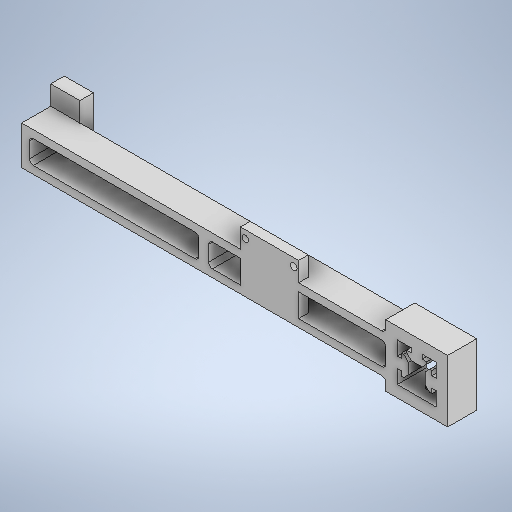
# Autodesk Inventor part: SUJETADOR_CAMARA_MODULO
Saved by Autodesk Inventor 2025.3 (Build 293356030, 356C)
## iProperties
Created: 2026-06-30
Part Number: SUJETADOR_CAMARA_MODULO
Material: Generic
Document SubType Name: Modeling
Designer: pablo
Density: 1 g/cm^3
Appearance: Default
Author: pablo
Autodesk Inventor part; units mm, degrees
ref_plane "YZ Plane" through (0, 0, 0) normal (1, 0, 0) x (0, 1, 0)
ref_plane "XZ Plane" through (0, 0, 0) normal (0, 1, 0) x (-1, 0, 0)
ref_plane "XY Plane" through (0, 0, 0) normal (0, 0, 1) x (1, 0, 0)
sketch "Sketch1" plane through (0, 0, 0) normal (0, 0, 1) x (1, 0, 0)
  line L0 (-2.8, -10) -> (-2.8, -7.8)
  line L1 (-2.8, -7.8) -> (-5.2, -7.8)
  line L2 (-5.2, -6.7) -> (-2.8, -4.3)
  line L3 (-7.8, -5.2) -> (-6.7, -5.2)
  line L4 (-6.7, -5.2) -> (-4.3, -2.8)
  line L5 (-2.8, -10) -> (-10, -10)
  line L6 (-7.8, -2.8) -> (-7.8, -5.2)
  line L7 (-7.8, -2.8) -> (-10, -2.8)
  line L8 (-10, -10) -> (-10, -2.8)
  line L9 (-5.2, -7.8) -> (-5.2, -6.7)
  line L10 (-4.3, -2.8) -> (-4.3, 0)
  line L11 (-4.3, 2.8) -> (-4.3, 0)
  line L12 (2.8, -10) -> (2.8, -7.8)
  line L13 (-10, -10) -> (10, -10)
  line L14 (2.8, -4.3) -> (0, -4.3)
  line L15 (5.2, -6.7) -> (2.8, -4.3)
  line L16 (6.7, -5.2) -> (4.3, -2.8)
  line L17 (2.8, -7.8) -> (5.2, -7.8)
  line L18 (2.8, -10) -> (10, -10)
  line L19 (5.2, -7.8) -> (5.2, -6.7)
  line L20 (-5.2, 6.7) -> (-2.8, 4.3)
  line L21 (-2.8, -4.3) -> (0, -4.3)
  line L22 (10, 10) -> (-10, 10)
  line L23 (2.8, 10) -> (10, 10)
  line L24 (-2.8, 7.8) -> (-5.2, 7.8)
  line L25 (-2.8, 10) -> (-2.8, 7.8)
  line L26 (2.8, 10) -> (2.8, 7.8)
  line L27 (2.8, 7.8) -> (5.2, 7.8)
  line L28 (-5.2, 7.8) -> (-5.2, 6.7)
  line L29 (5.2, 7.8) -> (5.2, 6.7)
  line L30 (-7.8, 5.2) -> (-6.7, 5.2)
  line L31 (-2.8, 4.3) -> (0, 4.3)
  line L32 (-6.7, 5.2) -> (-4.3, 2.8)
  line L33 (-7.8, 2.8) -> (-10, 2.8)
  line L34 (-7.8, 2.8) -> (-7.8, 5.2)
  line L35 (4.3, 2.8) -> (4.3, 0)
  line L36 (-10, 0) -> (10, 0) construction
  line L37 (10, -10) -> (10, 10)
  line L38 (-2.8, 10) -> (-10, 10)
  line L39 (0, -10) -> (0, 10) construction
  line L40 (-10, 10) -> (-10, 2.8)
  line L41 (7.8, 5.2) -> (6.7, 5.2)
  line L42 (2.8, 4.3) -> (0, 4.3)
  line L43 (5.2, 6.7) -> (2.8, 4.3)
  line L44 (7.8, 2.8) -> (10, 2.8)
  line L45 (6.7, 5.2) -> (4.3, 2.8)
  line L46 (7.8, 2.8) -> (7.8, 5.2)
  line L47 (10, 10) -> (10, 2.8)
  line L48 (7.8, -2.8) -> (10, -2.8)
  line L49 (7.8, -5.2) -> (6.7, -5.2)
  line L50 (7.8, -2.8) -> (7.8, -5.2)
  line L51 (10, 10) -> (10, -10) construction
  line L52 (10, -10) -> (10, -2.8)
  line L53 (4.3, -2.8) -> (4.3, 0)
  line L54 (-10, 10) -> (-10, -10)
  line L55 (16, 16) -> (-16, 16)
  line L56 (-16, 16) -> (-16, -16)
  line L57 (-16, -16) -> (16, -16)
  line L58 (16, -16) -> (16, 16)
  line L59 (16, 16) -> (-16, -16) construction
  line L60 (-16, 16) -> (16, -16) construction
  line L61 (-10, 10) -> (-16, 10)
  line L62 (-10, -10) -> (-16, -10)
  line L63 (-4.5, -16) -> (-12.5, -16)
  point P0 (0, 0)
  point P1 (0, 0)
  point P2 (0, 0)
  point P3 (-8.5, -16)
  point P4 (0, 0)
  point P5 (10, -2.8)
  dimension "d0" = 20
  dimension "d1" = 20
  dimension "d2" = 7.2
  dimension "d3" = 7.2
  dimension "d4" = 2.2
  dimension "d5" = 2.2
  dimension "d6" = 2.8
  dimension "d7" = 5.2
  dimension "d8" = 5.2
  dimension "d9" = 2.8
  dimension "d10" = 1.1
  dimension "d11" = 1.1
  dimension "d12" = 5.7
  dimension "d13" = 5.7
  dimension "d14" = 2.8
  dimension "d15" = 2.8
  dimension "d16" = 45
  dimension "d17" = 32
  dimension "d18" = 32
  constraints: 128 end point, 32 symmetric about line, 9 midpoint, 9 perpendicular, 7 point on line, 5 horizontal, 5 parallel, 2 coincident, 2 vertical, 1 horizontal alignment
  measures "d0" distance of L54.start L51.start
  measures "d1" distance of L51.start L13.end
  measures "d2" distance between parallel lines of L5 L7
  measures "d3" distance between parallel lines of L8 L0
  measures "d4" distance between parallel lines of L5 L1
  measures "d5" distance between parallel lines of L54 L6
  measures "d6" distance from line of L39.start L0
  measures "d7" distance from line of L39.start L9
  measures "d8" distance between parallel lines of L36 L3
  measures "d9" distance between parallel lines of L36 L7
  measures "d10" distance of L1.end L9.end
  measures "d11" distance of L6.end L4.start
  measures "d12" distance between parallel lines of L13 L21
  measures "d13" distance between parallel lines of L54 L10
  measures "d14" distance of L2.end L21.end
  measures "d15" distance of L10.start L10.end
  measures "d16" angle of L5 L2
  measures "d17" distance of L57.end L57.start
  measures "d18" distance between parallel lines of L55 L57
extrude "Extrusion1" add sketch "Sketch1" along normal blind 15 contours L13 L37 L22 L61 L56 L55 L58 L57 L62 L5 | L62 L56 L61 L40 L54 L8 | L54 L33 L34 L30 L32 L11 L10 L4 L3 L6 L7 | L48 L50 L49 L16 L53 L35 L45 L41 L46 L44 L37 | L22 L26 L27 L29 L43 L42 L31 L20 L28 L24 L25
sketch "Sketch2" plane through (-16, -16, 0) normal (0, -1, 0) x (1, 0, 0)
  line L0 (0, 0) -> (32, 0) projected
  line L1 (32, 0) -> (32, 15) projected
  line L2 (0, 15) -> (32, 15) projected
  line L3 (0, 0) -> (0, 15) projected
  point P0 (16, 0)
  point P1 (16, 7.5)
  point P2 (32, 7.5)
  point P3 (16, 0)
  constraints: 2 midpoint, 1 horizontal alignment, 1 vertical alignment
hole "Hole1" at (0, -16, 7.5) direction (0, 1, 0) diameter 4.2 depth 6
sketch "Sketch3" plane through (-16, -16, 0) normal (-1, 0, 0) x (0, 0, 1)
  line L0 (0, 32) -> (0, 0) projected
  line L1 (0, 0) -> (15, 0) projected
  line L2 (15, 32) -> (15, 0) projected
  line L3 (0, 32) -> (15, 32) projected
  line L4 (15, 26) -> (0, 26)
  line L5 (0, 26) -> (0, 22)
  line L6 (0, 22) -> (15, 22)
  line L7 (15, 22) -> (15, 26)
  line L8 (15, 10) -> (0, 10)
  line L9 (0, 10) -> (0, 6)
  line L10 (0, 6) -> (15, 6)
  line L11 (15, 6) -> (15, 10)
  line L12 (0, 32) -> (0, 0) projected
  point P0 (0, 16)
  point P1 (15, 8)
  point P2 (0, 16)
  point P3 (15, 24)
  point P4 (0, 16)
  dimension "d31" = 4
  dimension "d32" = 8
  dimension "d33" = 8
  dimension "d34" = 4
  constraints: 16 end point, 4 parallel, 4 point on line, 3 midpoint, 2 horizontal, 2 perpendicular, 2 other
  measures "d31" distance between parallel lines of L10 L8
  measures "d32" vertical distance of point (15, 8) point (0, 16)
  measures "d33" vertical distance of point (15, 24) point (0, 16)
  measures "d34" distance between parallel lines of L4 L6
extrude "Extrusion2" add sketch "Sketch3" along normal blind 188 contours L4 L2 L6 L0 | L8 L2 L10 L0
sketch "Sketch4" plane through (-16, 6, 0) normal (0, -1, 0) x (1, 0, 0)
  line L0 (0, 15) -> (0, 0) projected
  line L1 (0, 15) -> (-188, 15) projected
  line L2 (-188, 0) -> (-188, 15) projected
  line L3 (0, 0) -> (-188, 0) projected
  line L4 (0, 0) -> (-188, 0) projected
  line L5 (0, 15) -> (-188, 15) projected
  line L6 (-91.5, 0) -> (-96.5, 0)
  line L7 (-96.5, 0) -> (-96.5, 15)
  line L8 (-96.5, 15) -> (-91.5, 15)
  line L9 (-91.5, 15) -> (-91.5, 0)
  point P0 (16, 0)
  point P1 (-94, 15)
  point P2 (-94, 15)
  point P3 (-91.5, 0)
  point P4 (-96.5, 0)
  dimension "d37" = 5
  constraints: 8 end point, 2 midpoint, 2 parallel, 2 point on line, 1 coincident, 1 horizontal, 1 perpendicular
  measures "d37" distance between parallel lines of L7 L9
extrude "Extrusion3" add sketch "Sketch4" along normal up to surface (12 mm away) contours L9 L3 L7 L1
sketch "Sketch9" plane through (0, 0, 15) normal (0, 0, 1) x (1, 0, 0)
  line L0 (-112.5, 6) -> (-204, 6) projected
  line L1 (-112.5, 6) -> (-112.5, -6) projected
  line L2 (-112.5, -6) -> (-204, -6) projected
  line L3 (-16, 6) -> (-107.5, 6) projected
  line L4 (-16, 6) -> (-16, -6) projected
  line L5 (-16, -6) -> (-107.5, -6) projected
  line L6 (-107.5, 6) -> (-107.5, -6) projected
  line L7 (-16, -10) -> (-204, -10) projected
  line L8 (-16, -10) -> (-16, -16) projected
  line L9 (-16, -16) -> (16, -16) projected
  line L10 (16, -16) -> (16, 16) projected
  line L11 (16, 16) -> (-16, 16) projected
  line L12 (-16, 16) -> (-16, 10) projected
  line L13 (-16, 10) -> (-204, 10) projected
  line L14 (-10, -10) -> (-10, -2.8) projected
  line L15 (-10, -2.8) -> (-7.8, -2.8) projected
  line L16 (-7.8, -2.8) -> (-7.8, -5.2) projected
  line L17 (-7.8, -5.2) -> (-6.7, -5.2) projected
  line L18 (-6.7, -5.2) -> (-4.3, -2.8) projected
  line L19 (-4.3, -2.8) -> (-4.3, 2.8) projected
  line L20 (-4.3, 2.8) -> (-6.7, 5.2) projected
  line L21 (-6.7, 5.2) -> (-7.8, 5.2) projected
  line L22 (-7.8, 5.2) -> (-7.8, 2.8) projected
  line L23 (-7.8, 2.8) -> (-10, 2.8) projected
  line L24 (-10, 2.8) -> (-10, 10) projected
  line L25 (-10, 10) -> (-2.8, 10) projected
  line L26 (-2.8, 10) -> (-2.8, 7.8) projected
  line L27 (-2.8, 7.8) -> (-5.2, 7.8) projected
  line L28 (-5.2, 7.8) -> (-5.2, 6.7) projected
  line L29 (-5.2, 6.7) -> (-2.8, 4.3) projected
  line L30 (-2.8, 4.3) -> (2.8, 4.3) projected
  line L31 (2.8, 4.3) -> (5.2, 6.7) projected
  line L32 (5.2, 6.7) -> (5.2, 7.8) projected
  line L33 (5.2, 7.8) -> (2.8, 7.8) projected
  line L34 (2.8, 7.8) -> (2.8, 10) projected
  line L35 (2.8, 10) -> (10, 10) projected
  line L36 (10, 10) -> (10, 2.8) projected
  line L37 (10, 2.8) -> (7.8, 2.8) projected
  line L38 (7.8, 2.8) -> (7.8, 5.2) projected
  line L39 (7.8, 5.2) -> (6.7, 5.2) projected
  line L40 (6.7, 5.2) -> (4.3, 2.8) projected
  line L41 (4.3, 2.8) -> (4.3, -2.8) projected
  line L42 (4.3, -2.8) -> (6.7, -5.2) projected
  line L43 (6.7, -5.2) -> (7.8, -5.2) projected
  line L44 (7.8, -5.2) -> (7.8, -2.8) projected
  line L45 (7.8, -2.8) -> (10, -2.8) projected
  line L46 (10, -2.8) -> (10, -10) projected
  line L47 (10, -10) -> (-10, -10) projected
  line L48 (-61, 20) -> (-91, 20)
  line L49 (-91, 20) -> (-91, -10)
  line L50 (-91, -10) -> (-61, -10)
  line L51 (-61, -10) -> (-61, 20)
  line L52 (-16, -10) -> (-204, -10) projected
  line L53 (-204, -10) -> (-204, -6) projected
  line L54 (-204, 6) -> (-204, 10) projected
  point P0 (0, 0)
  point P1 (-16, 0)
  point P2 (-76, -10)
  dimension "d58" = 30
  dimension "d59" = 30
  dimension "d60" = 45
  constraints: 8 end point, 2 midpoint, 2 parallel, 1 horizontal, 1 perpendicular, 1 point on line
  measures "d58" distance of L49.end L50.end
  measures "d59" distance of L50.end L48.start
  measures "d60" distance between parallel lines of L8 L51
extrude "Extrusion7" add sketch "Sketch9" against normal blind 5 contours L49 L48 L51 L13 | L13 L51 L3 L49 | L3 L51 L5 L49 | L49 L5 L51 L7
sketch "Sketch10" plane through (0, 0, 15) normal (0, 0, 1) x (1, 0, 0)
  line L0 (-16, 6) -> (-61, 6) projected
  line L1 (-16, 6) -> (-16, -6) projected
  line L2 (-16, -6) -> (-61, -6) projected
  line L3 (-61, -6) -> (-61, 6) projected
  line L4 (-91, 6) -> (-91, -6) projected
  line L5 (-91, -6) -> (-107.5, -6) projected
  line L6 (-107.5, 6) -> (-107.5, -6) projected
  line L7 (-91, 6) -> (-107.5, 6) projected
  line L8 (-112.5, 6) -> (-204, 6) projected
  line L9 (-112.5, 6) -> (-112.5, -6) projected
  line L10 (-112.5, -6) -> (-204, -6) projected
  line L11 (-91, 10) -> (-204, 10) projected
  line L12 (-16, -10) -> (-204, -10) projected
  line L13 (-16, -10) -> (-16, -16) projected
  line L14 (-16, -16) -> (16, -16) projected
  line L15 (16, -16) -> (16, 16) projected
  line L16 (16, 16) -> (-16, 16) projected
  line L17 (-16, 16) -> (-16, 10) projected
  line L18 (-16, 10) -> (-61, 10) projected
  line L19 (-61, 10) -> (-61, 20) projected
  line L20 (-61, 20) -> (-91, 20) projected
  line L21 (-91, 20) -> (-91, 10) projected
  line L22 (-10, -10) -> (-10, -2.8) projected
  line L23 (-10, -2.8) -> (-7.8, -2.8) projected
  line L24 (-7.8, -2.8) -> (-7.8, -5.2) projected
  line L25 (-7.8, -5.2) -> (-6.7, -5.2) projected
  line L26 (-6.7, -5.2) -> (-4.3, -2.8) projected
  line L27 (-4.3, -2.8) -> (-4.3, 2.8) projected
  line L28 (-4.3, 2.8) -> (-6.7, 5.2) projected
  line L29 (-6.7, 5.2) -> (-7.8, 5.2) projected
  line L30 (-7.8, 5.2) -> (-7.8, 2.8) projected
  line L31 (-7.8, 2.8) -> (-10, 2.8) projected
  line L32 (-10, 2.8) -> (-10, 10) projected
  line L33 (-10, 10) -> (-2.8, 10) projected
  line L34 (-2.8, 10) -> (-2.8, 7.8) projected
  line L35 (-2.8, 7.8) -> (-5.2, 7.8) projected
  line L36 (-5.2, 7.8) -> (-5.2, 6.7) projected
  line L37 (-5.2, 6.7) -> (-2.8, 4.3) projected
  line L38 (-2.8, 4.3) -> (2.8, 4.3) projected
  line L39 (2.8, 4.3) -> (5.2, 6.7) projected
  line L40 (5.2, 6.7) -> (5.2, 7.8) projected
  line L41 (5.2, 7.8) -> (2.8, 7.8) projected
  line L42 (2.8, 7.8) -> (2.8, 10) projected
  line L43 (2.8, 10) -> (10, 10) projected
  line L44 (10, 10) -> (10, 2.8) projected
  line L45 (10, 2.8) -> (7.8, 2.8) projected
  line L46 (7.8, 2.8) -> (7.8, 5.2) projected
  line L47 (7.8, 5.2) -> (6.7, 5.2) projected
  line L48 (6.7, 5.2) -> (4.3, 2.8) projected
  line L49 (4.3, 2.8) -> (4.3, -2.8) projected
  line L50 (4.3, -2.8) -> (6.7, -5.2) projected
  line L51 (6.7, -5.2) -> (7.8, -5.2) projected
  line L52 (7.8, -5.2) -> (7.8, -2.8) projected
  line L53 (7.8, -2.8) -> (10, -2.8) projected
  line L54 (10, -2.8) -> (10, -10) projected
  line L55 (10, -10) -> (-10, -10) projected
  line L56 (-204, 6) -> (-204, 10) projected
  line L57 (-204, -10) -> (-204, -6) projected
  point P0 (0, 0)
  point P1 (-63.5, 16)
  point P2 (-88.5, 16)
  dimension "d63" = 2.5
  dimension "d64" = 4
  dimension "d65" = 2.5
  constraints: 1 horizontal alignment
  measures "d63" distance from line of L19 point (-63.5, 16)
  measures "d64" distance from line of L20 point (-63.5, 16)
  measures "d65" distance from line of L21 point (-88.5, 16)
hole "Hole3" at (-63.5, 16, 15) at (-88.5, 16, 15) direction (0, 0, -1) diameter 3.4 depth 5
sketch "Sketch11" plane through (-204, 6, 0) normal (0, -1, 0) x (1, 0, 0)
  line L0 (91.5, 0) -> (0, 0) projected
  line L1 (4, 0) -> (4, 15)
  line L2 (91.5, 15) -> (0, 15) projected
  line L3 (0, 0) -> (0, 15) projected
  point P0 (204, 0)
  dimension "d73" = 4
  constraints: 2 end point, 2 point on line, 1 vertical
  measures "d73" distance between parallel lines of L3 L1
extrude "Extrusion8" add sketch "Sketch11" along normal up to surface (12 mm away)
fillet "Fillet1" radius 2 10 edges at (-200, 6, 7.5) (-200, -6, 7.5) (-112.5, 6, 7.5) (-112.5, -6, 7.5) (-107.5, 6, 7.5) (-107.5, -6, 7.5) (-16, 6, 7.5) (-16, -6, 7.5) (-16, -10, 7.5) (-16, 10, 7.5)
sketch "Sketch12" plane through (0, 0, 0) normal (0, 0, -1) x (-1, 0, 0)
  line L0 (204, 10) -> (204, -10) projected
  line L1 (18, 10) -> (204, 10) projected
  arc A0 (16, 12) -> (18, 10) centre (18, 12) ccw projected
  line L2 (16, 16) -> (16, 12) projected
  line L3 (-16, 16) -> (16, 16) projected
  line L4 (-16, -16) -> (-16, 16) projected
  line L5 (16, -16) -> (-16, -16) projected
  line L6 (16, -12) -> (16, -16) projected
  arc A1 (18, -10) -> (16, -12) centre (18, -12) ccw projected
  line L7 (18, -10) -> (204, -10) projected
  line L8 (200, 4) -> (200, -4) projected
  arc A2 (198, -6) -> (200, -4) centre (198, -4) ccw projected
  line L9 (114.5, -6) -> (198, -6) projected
  arc A3 (112.5, -4) -> (114.5, -6) centre (114.5, -4) ccw projected
  line L10 (112.5, 4) -> (112.5, -4) projected
  arc A4 (114.5, 6) -> (112.5, 4) centre (114.5, 4) ccw projected
  line L11 (114.5, 6) -> (198, 6) projected
  arc A5 (200, 4) -> (198, 6) centre (198, 4) ccw projected
  line L12 (107.5, 4) -> (107.5, -4) projected
  arc A6 (105.5, -6) -> (107.5, -4) centre (105.5, -4) ccw projected
  line L13 (18, -6) -> (105.5, -6) projected
  arc A7 (16, -4) -> (18, -6) centre (18, -4) ccw projected
  line L14 (16, 4) -> (16, -4) projected
  arc A8 (18, 6) -> (16, 4) centre (18, 4) ccw projected
  line L15 (18, 6) -> (105.5, 6) projected
  arc A9 (107.5, 4) -> (105.5, 6) centre (105.5, 4) ccw projected
  line L16 (10, -10) -> (10, -2.8) projected
  line L17 (-10, -10) -> (10, -10) projected
  line L18 (-10, -2.8) -> (-10, -10) projected
  line L19 (-7.8, -2.8) -> (-10, -2.8) projected
  line L20 (-7.8, -5.2) -> (-7.8, -2.8) projected
  line L21 (-6.7, -5.2) -> (-7.8, -5.2) projected
  line L22 (-4.3, -2.8) -> (-6.7, -5.2) projected
  line L23 (-4.3, 2.8) -> (-4.3, -2.8) projected
  line L24 (-6.7, 5.2) -> (-4.3, 2.8) projected
  line L25 (-7.8, 5.2) -> (-6.7, 5.2) projected
  line L26 (-7.8, 2.8) -> (-7.8, 5.2) projected
  line L27 (-10, 2.8) -> (-7.8, 2.8) projected
  line L28 (-10, 10) -> (-10, 2.8) projected
  line L29 (-2.8, 10) -> (-10, 10) projected
  line L30 (-2.8, 7.8) -> (-2.8, 10) projected
  line L31 (-5.2, 7.8) -> (-2.8, 7.8) projected
  line L32 (-5.2, 6.7) -> (-5.2, 7.8) projected
  line L33 (-2.8, 4.3) -> (-5.2, 6.7) projected
  line L34 (2.8, 4.3) -> (-2.8, 4.3) projected
  line L35 (5.2, 6.7) -> (2.8, 4.3) projected
  line L36 (5.2, 7.8) -> (5.2, 6.7) projected
  line L37 (2.8, 7.8) -> (5.2, 7.8) projected
  line L38 (2.8, 10) -> (2.8, 7.8) projected
  line L39 (10, 10) -> (2.8, 10) projected
  line L40 (10, 2.8) -> (10, 10) projected
  line L41 (7.8, 2.8) -> (10, 2.8) projected
  line L42 (7.8, 5.2) -> (7.8, 2.8) projected
  line L43 (6.7, 5.2) -> (7.8, 5.2) projected
  line L44 (4.3, 2.8) -> (6.7, 5.2) projected
  line L45 (4.3, -2.8) -> (4.3, 2.8) projected
  line L46 (6.7, -5.2) -> (4.3, -2.8) projected
  line L47 (7.8, -5.2) -> (6.7, -5.2) projected
  line L48 (7.8, -2.8) -> (7.8, -5.2) projected
  line L49 (10, -2.8) -> (7.8, -2.8) projected
  line L50 (189, -20) -> (204, -20)
  line L51 (204, -20) -> (204, 20)
  line L52 (204, 20) -> (189, 20)
  line L53 (189, 20) -> (189, -20)
  point P0 (0, 0)
  point P1 (189, 0)
  point P2 (200, 0)
  point P3 (204, 0)
  dimension "d77" = 15
  dimension "d78" = 40
  constraints: 8 end point, 4 midpoint, 2 parallel, 1 horizontal, 1 horizontal alignment, 1 perpendicular
  measures "d77" distance of L51.end L52.end
  measures "d78" distance of L50.end L51.end
extrude "Extrusion9" add sketch "Sketch12" along normal blind 7 contours L0 L7 L53 L9 A2 L8 A5 L11 L1 | L1 L53 L52 L51 | L51 L50 L53 L7 | L11 A5 L8 A2 L9 L53
sketch "Sketch13" plane through (0, 0, -7) normal (0, 0, -1) x (-1, 0, 0)
  line L0 (189, 20) -> (189, -20) projected
  line L1 (189, -20) -> (204, -20) projected
  line L2 (204, -20) -> (204, 20) projected
  line L3 (204, 20) -> (189, 20) projected
  line L4 (191.25, -18.25) -> (201.75, -18.25)
  line L5 (201.75, -18.25) -> (201.75, 18.25)
  line L6 (201.75, 18.25) -> (191.25, 18.25)
  line L7 (191.25, 18.25) -> (191.25, -18.25)
  line L8 (191.25, -18.25) -> (201.75, 18.25) construction
  line L9 (201.75, -18.25) -> (191.25, 18.25) construction
  point P0 (0, 0)
  point P1 (196.5, 0)
  point P2 (196.5, 20)
  point P3 (189, 0)
  dimension "d81" = 10.5
  dimension "d82" = 36.5
  constraints: 12 end point, 4 midpoint, 2 parallel, 1 horizontal, 1 horizontal alignment, 1 perpendicular, 1 vertical alignment
  measures "d81" distance of L5.end L6.end
  measures "d82" distance of L4.end L5.end
extrude "Extrusion10" cut sketch "Sketch13" against normal blind 3 contours L7 L6 L5 L4
sketch "Sketch14" plane through (0, 0, 0) normal (0, 0, 1) x (1, 0, 0)
  line L0 (-189, 6) -> (-198, 6) projected
  arc A0 (-198, 6) -> (-200, 4) centre (-198, 4) ccw projected
  line L1 (-200, 4) -> (-200, -4) projected
  arc A1 (-200, -4) -> (-198, -6) centre (-198, -4) ccw projected
  line L2 (-189, -6) -> (-198, -6) projected
  line L3 (-189, 6) -> (-189, -6) projected
  line L4 (-189, -10) -> (-204, -10) projected
  line L5 (-204, -20) -> (-204, -10) projected
  line L6 (-189, -20) -> (-204, -20) projected
  line L7 (-189, -10) -> (-189, -20) projected
  line L8 (-189, 10) -> (-204, 10) projected
  line L9 (-189, 20) -> (-189, 10) projected
  line L10 (-204, 20) -> (-189, 20) projected
  line L11 (-204, 10) -> (-204, 20) projected
  line L12 (-196.5, -3.2909) -> (-199.35, -1.6454)
  line L13 (-199.35, -1.6454) -> (-199.35, 1.6454)
  line L14 (-199.35, 1.6454) -> (-196.5, 3.2909)
  line L15 (-196.5, 3.2909) -> (-193.65, 1.6454)
  line L16 (-193.65, 1.6454) -> (-193.65, -1.6454)
  line L17 (-193.65, -1.6454) -> (-196.5, -3.2909)
  line L18 (-204, 20) -> (-189, 20) projected
  point P0 (0, 0)
  point P1 (-196.5, 0)
  point P2 (-196.5, 20)
  point P3 (-189, 0)
  point P4 (-196.5, 0)
  point P5 (-196.5, 20)
  dimension "d85" = 5.7
  constraints: 12 end point, 3 midpoint, 2 vertical alignment, 1 coincident, 1 horizontal alignment, 13 other
  measures "d85" distance between parallel lines of L14 L17
extrude "Extrusion11" cut sketch "Sketch14" against normal blind 2.6 contours L12 L13 L14 L15 L16 L17
sketch "Sketch15" plane through (0, 0, -4) normal (0, 0, -1) x (-1, 0, 0)
  line L0 (201.75, 18.25) -> (201.75, -18.25) projected
  line L1 (191.25, 18.25) -> (201.75, 18.25) projected
  line L2 (191.25, -18.25) -> (191.25, 18.25) projected
  line L3 (201.75, -18.25) -> (191.25, -18.25) projected
  line L4 (201.75, -18.25) -> (191.25, -18.25) projected
  line L5 (191.25, -18.25) -> (191.25, 18.25) projected
  point P0 (0, 0)
  point P1 (196.5, 0)
  point P2 (196.5, -18.25)
  point P3 (191.25, 0)
  constraints: 2 midpoint, 1 horizontal alignment, 1 vertical alignment
hole "Hole4" at (-196.5, 0, -4) direction (0, 0, 1) diameter 3.4 depth 1.4
sketch "Sketch16" plane through (0, 0, -7) normal (0, 0, -1) x (-1, 0, 0)
  line L0 (191.25, 18.25) -> (201.75, 18.25) projected
  line L1 (201.75, 18.25) -> (201.75, -18.25) projected
  line L2 (201.75, -18.25) -> (191.25, -18.25) projected
  line L3 (191.25, -18.25) -> (191.25, 18.25) projected
  line L4 (189, 20) -> (189, -20) projected
  line L5 (189, -20) -> (204, -20) projected
  line L6 (204, -20) -> (204, 20) projected
  line L7 (204, 20) -> (189, 20) projected
  line L8 (201.75, -11) -> (204, -11)
  line L9 (204, 11) -> (201.75, 11)
  point P0 (0, 0)
  point P1 (201.75, 0)
  dimension "d95" = 22
  dimension "d96" = 11
  constraints: 4 end point, 4 point on line, 2 perpendicular, 1 midpoint
  measures "d95" distance between parallel lines of L8 L9
  measures "d96" distance from line of point (201.75, 0) L9
extrude "Extrusion12" cut sketch "Sketch16" against normal up to surface (3 mm away) contours L9 L6 L8 L1
equation "\"d1\" = d0"
equation "\"d2\" = d3"
equation "\"d5\" = d4"
equation "\"d8\" = d7"
equation "\"d11\" = d10"
equation "\"d13\" = d12"
equation "\"d18\" = d17"
equation "\"d96\" = 0.5 * d95"
body "Solid1"
